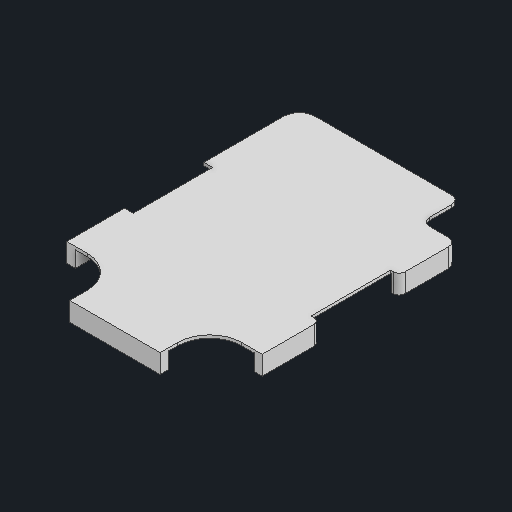
# Autodesk Inventor part: 电池支撑
Saved by Autodesk Inventor 2025 (Build 290162000, 162)
## iProperties
Created: 2025-12-04
Part Number: 电池支撑
Material: 常规
Document SubType Name: Modeling
Designer: HZD
Density: 1 g/cm^3
Appearance: 默认
Author: HZD
Autodesk Inventor part; units mm, degrees
ref_plane "YZ Plane" through (0, 0, 0) normal (1, 0, 0) x (0, 1, 0)
ref_plane "XZ Plane" through (0, 0, 0) normal (0, 1, 0) x (-1, 0, 0)
ref_plane "XY Plane" through (0, 0, 0) normal (0, 0, 1) x (1, 0, 0)
sketch "草图3" plane through (0, 0, 0) normal (0, 1, 0) x (-1, 0, 0)
  line L0 (-33.5, 46.5) -> (33.5, 46.5)
  line L1 (33.5, 46.5) -> (33.5, -50.2514)
  line L2 (33.5, -50.2514) -> (-33.5, -50.2514)
  line L3 (-33.5, -50.2514) -> (-33.5, 46.5)
  line L4 (-8.5685, -50.2514) -> (8.4315, -50.2514) projected
  point P0 (0, 0)
  dimension "d3" = 67
  constraints: 8 end point, 2 parallel, 1 collinear, 1 horizontal, 1 perpendicular
  measures "d3" distance of L1.end L2.end
extrude "拉伸2" add sketch "草图3" along normal blind 1
sketch "草图4" plane through (0, 1, 0) normal (0, 1, 0) x (1, 0, 0)
  line L0 (33.5, -46.5) -> (33.5, 50.2514) projected
  line L1 (33.5, 37.1516) -> (21.5, 37.1516)
  line L2 (21.5, 37.1516) -> (21.5, 51.3016)
  line L3 (21.5, 51.3016) -> (33.5, 51.3016) construction
  line L4 (33.5, 51.3016) -> (33.5, 37.1516)
  line L5 (33.5, 51.3016) -> (21.5, 51.3016)
  point P0 (0, 0)
  dimension "d7" = 12
  constraints: 10 end point, 3 equal length, 1 horizontal, 1 perpendicular, 1 point on line
  measures "d7" distance of L1.start L1.end
extrude "拉伸3" cut sketch "草图4" against normal blind 1
fillet "圆角1" radius 2.75 3 edges at (33.5, 0.5, -37.1516) (21.5, 0.5, -50.2514) (21.5, 0.5, -37.1516)
sketch "草图5" plane through (0, 0, 0) normal (0, -1, 0) x (1, 0, 0)
  line L0 (-33.5, 46.5) -> (33.5, 46.5) projected
  line L1 (-33.5, -50.2514) -> (-33.5, 46.5) projected
  line L2 (33.5, 46.5) -> (-33.5, 46.5)
  line L3 (-33.5, 46.5) -> (-33.5, 43.5)
  line L4 (-33.5, 43.5) -> (33.5, 43.5)
  line L5 (33.5, 43.5) -> (33.5, 46.5)
  point P0 (0, 0)
  dimension "d11" = 3
  constraints: 8 end point, 2 parallel, 1 horizontal, 1 perpendicular, 1 point on line
  measures "d11" distance between parallel lines of L0 L4
extrude "拉伸4" add sketch "草图5" along normal blind 5.5
sketch "草图6" plane through (0, 0, 0) normal (0, -1, 0) x (1, 0, 0)
  line L0 (33.5, 43.5) -> (33.5, -34.4016) projected
  line L1 (24.25, -37.1516) -> (30.75, -37.1516) projected
  line L2 (33.5, 43.5) -> (30.75, 43.5)
  line L3 (30.75, 43.5) -> (30.75, -37.1516)
  line L4 (30.75, -37.1516) -> (33.5, -37.1516)
  line L5 (33.5, -37.1516) -> (33.5, 43.5)
  arc A0 (30.75, -37.1516) -> (33.5, -34.4016) centre (30.75, -34.4016) ccw projected
  point P0 (0, 0)
  point P1 (33.5, -34.4016)
  constraints: 8 end point, 2 parallel, 1 horizontal, 1 perpendicular
extrude "拉伸5" add sketch "草图6" along normal up to surface (5.5 mm away) contours L0 A0 L3 L2
fillet "圆角3" radius 2 3 edges at (33.5, -2.25, 46.5) (30.75, -2.75, 43.5) (-33.5, -2.25, 46.5)
sketch "草图7" plane through (0, 0, 0) normal (0, -1, 0) x (1, 0, 0)
  line L0 (28.75, 43.5) -> (-33.5, 43.5) projected
  line L1 (-33.5, 43.5) -> (-30.5, 43.5)
  line L2 (-30.5, 43.5) -> (-30.5, 13.5)
  line L3 (-30.5, 13.5) -> (-33.5, 13.5)
  line L4 (-33.5, 13.5) -> (-33.5, 43.5)
  point P0 (0, 0)
  dimension "d18" = 3
  dimension "d19" = 30
  constraints: 8 end point, 2 parallel, 1 horizontal, 1 perpendicular
  measures "d18" distance between parallel lines of L4 L2
  measures "d19" distance between parallel lines of L0 L3
extrude "拉伸6" add sketch "草图7" along normal up to surface (5.5 mm away)
fillet "圆角4" radius 2 1 edges at (-33.5, -2.75, 13.5)
fillet "圆角5" radius 5.5 1 edges at (-33.5, 0.5, -50.2514)
sketch "草图8" plane through (0, 1, 0) normal (0, 1, 0) x (1, 0, 0)
  line L0 (33.5, -44.5) -> (33.5, 34.4016) projected
  line L1 (33.5, -29.5) -> (15.5, -29.5)
  line L2 (15.5, -29.5) -> (15.5, -46.5)
  line L3 (15.5, -46.5) -> (33.5, -46.5)
  line L4 (33.5, -46.5) -> (33.5, -29.5)
  line L5 (31.5, -46.5) -> (-31.5, -46.5) projected
  line L6 (0, -46.5) -> (0, -34.1358)
  line L7 (-33.5, -29.5) -> (-15.5, -29.5)
  line L8 (-15.5, -29.5) -> (-15.5, -46.5)
  line L9 (-15.5, -46.5) -> (-33.5, -46.5)
  line L10 (-33.5, -46.5) -> (-33.5, -29.5)
  point P0 (0, 0)
  point P1 (-33.5, -44.5)
  point P2 (-31.5, -46.5)
  dimension "d24" = 18
  dimension "d25" = 17
  constraints: 18 end point, 5 symmetric about line, 2 parallel, 1 collinear, 1 horizontal, 1 midpoint, 1 perpendicular, 1 point on line, 1 vertical
  measures "d24" distance of L2.end L3.end
  measures "d25" distance between parallel lines of L1 L3
extrude "拉伸7" cut sketch "草图8" against normal blind 20.5
fillet "圆角6" radius 11 2 edges at (-15.5, 0.5, 29.5) (15.5, 0.5, 29.5)
sketch "草图9" plane through (0, 1, 0) normal (0, 1, 0) x (1, 0, 0)
  line L0 (42.0685, 31.3684) -> (36.3257, 31.3684) projected
  line L1 (36.3257, 31.3684) -> (36.3257, 17.4684) projected
  line L2 (36.3257, 17.4684) -> (33.9498, 17.4684) projected
  line L3 (33.9498, 17.4684) -> (33.9498, -9.7316) projected
  line L4 (33.9498, -9.7316) -> (36.3257, -9.7316) projected
  line L5 (36.3257, -23.6316) -> (36.3257, -9.7316) projected
  line L6 (36.3257, -23.6316) -> (42.0685, -23.6316) projected
  line L7 (42.0685, -23.6316) -> (42.0685, 31.3684) projected
  line L8 (36.3257, 17.4684) -> (30.5, 17.4684)
  line L9 (30.5, 17.4684) -> (30.5, -9.7316)
  line L10 (30.5, -9.7316) -> (36.3257, -9.7316)
  line L11 (36.3257, -9.7316) -> (36.3257, 17.4684)
  line L12 (33.5, -29.5) -> (33.5, 34.4016) projected
  point P0 (0, 0)
  point P1 (33.5, -9.7316)
  point P2 (33.5, 17.4684)
  dimension "d29" = 3
  constraints: 8 end point, 2 parallel, 1 horizontal, 1 perpendicular
  measures "d29" distance between parallel lines of L9 L12
extrude "拉伸8" cut sketch "草图9" against normal blind 20.5 contours L12 L10 L9 L8
fillet "圆角7" radius 2 2 edges at (33.5, -2.25, 9.7316) (33.5, -2.25, -17.4684)
mirror "镜像1" about plane through (0, 0, 0) normal (1, 0, 0) of "拉伸8"
